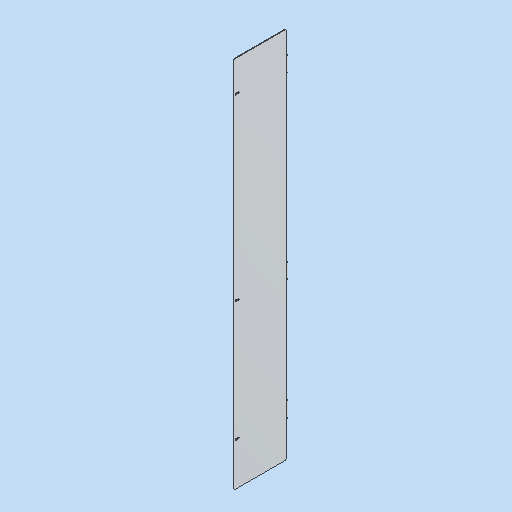
# Autodesk Inventor part: MM0948AN180_G01_108
Saved by Autodesk Inventor 2023.3 (Build 273359000, 359)
## iProperties
Created: 2023-08-14
Part Number: MM0948AN180_G01_108
Material: 3.3535 AlMg3 - AW 5754 (Blech)
Description: =<RBPARTNOTITLE2>
Document SubType Name: Sheet Metal
Designer: RIC7AN
Mass: 965.696 g
Surface Area: 3636.47 cm^2
Volume: 357.798 cm^3
Density: 2.699 g/cm^3
Flat Pattern Width: 19.1095 cm
Flat Pattern Length: 111.3 cm
Flat Pattern Area: 2126.88 cm^2
Sheet Metal Rule: Standard_mm
Sheet Metal Width: 191,095 mm
Sheet Metal Length: 1113,000 mm
Sheet Metal Area: 212688,390 mm^2
Appearance: Aluminium AnP
RBPARTMADEOF: 2 x 191,095 x 1113 (FM)
RBDRAWINGMISSINGSPEC: --
AnP_Kategorie: 1
RBPARTNOTITLE2: Anfertigungsteil
RBSURFACE: --
RBPARTNOTITLE1: manufactured part
RBSURFACE2: eloxiert E6/EV1 aluminiumfarbig
AnP_Material: =<Material>
RBMATERIAL: =<Material>
RBMATNO: =<Part Number>
RBPARTNO: SIEHE MNR
MaxAbmaße: 2 x 191,095 x 1113 (FM)
Author: RIC7AN
Keywords: =<RBPARTMADEOF>
Comments: =<RBSURFACE2>
Revision Number: 01
Autodesk Inventor part; units mm, degrees
ref_plane "YZ Plane" through (0, 0, 0) normal (1, 0, 0) x (0, 1, 0)
ref_plane "XZ Plane" through (0, 0, 0) normal (0, 1, 0) x (-1, 0, 0)
ref_plane "XY Plane" through (0, 0, 0) normal (0, 0, 1) x (1, 0, 0)
sketch "Skizze1" plane through (0, 0, 0) normal (0, 0, 1) x (1, 0, 0)
  line L0 (-31, 0) -> (0, 0)
  line L1 (0, 0) -> (0, -164)
  dimension "d0" = 31
  dimension "d1" = 164
  measures "d0" distance of L0.start L0.end
  measures "d1" distance of L0.end L1.end
contour flange "Konturlasche1" sketch "Skizze1" thickness 2 bend radius 3 width 1113 along (0, 0, 1) mid plane no both sides no wall seen from (-15.5, 0, 0) lies toward (0, -1, 0) curves L0 L1
bend "Biegung1"
corner "Ecke1"
sketch "Skizze2" plane through (0, -164, 1113) normal (1, 0, 0) x (0, 0, -1)
  line L0 (1113, 164) -> (0, 164) projected
  line L1 (0, 164) -> (70, 164)
  line L2 (70, 164) -> (70, 157)
  line L3 (70, 157) -> (0, 157)
  line L4 (0, 157) -> (0, 164)
  line L5 (1113, 164) -> (649.5, 164)
  line L6 (649.5, 164) -> (649.5, 157)
  line L7 (649.5, 157) -> (1113, 157)
  line L8 (1113, 157) -> (1113, 164)
  line L9 (115, 164) -> (604.5, 164)
  line L10 (604.5, 164) -> (604.5, 157)
  line L11 (604.5, 157) -> (115, 157)
  line L12 (115, 157) -> (115, 164)
  line L13 (1008, 164) -> (963, 164)
  line L14 (963, 164) -> (963, 157)
  line L15 (963, 157) -> (1008, 157)
  line L16 (1008, 157) -> (1008, 164)
  line L17 (1113, 159) -> (1113, 0) projected
  point P0 (649.5, 164)
  dimension "d13" = 70
  dimension "d14" = 7
  dimension "d15" = 45
  dimension "d16" = 45
  dimension "d19" = 534.5
  dimension "d20" = 45
  dimension "d21" = 150
  constraints: 32 end point, 8 parallel, 4 horizontal, 4 perpendicular, 3 point on line, 2 collinear
  measures "d13" distance of L2.end L3.end
  measures "d14" distance between parallel lines of L0 L3
  measures "d15" distance between parallel lines of L12 L2
  measures "d16" distance between parallel lines of L6 L10
  measures "d19" distance between parallel lines of L10 L2
  measures "d20" distance between parallel lines of L16 L14
  measures "d21" distance between parallel lines of L17 L14
extrude "Extrusion1" cut sketch "Skizze2" against normal through all contours L8 L7 L16 L0 | L14 L7 L6 L0 | L10 L11 L12 L0 | L2 L3 L4 L0
sketch "Skizze3" plane through (-31, -2, 1043) normal (0, -1, 0) x (1, 0, 0)
  line L0 (8, -22.5) -> (16, -22.5) construction
  line L1 (8, -19.2) -> (16, -19.2)
  line L2 (16, -25.8) -> (8, -25.8)
  arc A0 (8, -19.2) -> (8, -25.8) centre (8, -22.5) ccw
  arc A1 (16, -25.8) -> (16, -19.2) centre (16, -22.5) ccw
  line L3 (0, -45) -> (0, 0) projected
  line L4 (26, 0) -> (0, 0) projected
  line L5 (8, -557) -> (16, -557) construction
  line L6 (8, -553.7) -> (16, -553.7)
  line L7 (16, -560.3) -> (8, -560.3)
  arc A2 (8, -553.7) -> (8, -560.3) centre (8, -557) ccw
  arc A3 (16, -560.3) -> (16, -553.7) centre (16, -557) ccw
  line L8 (8, -915.5) -> (16, -915.5) construction
  line L9 (8, -912.2) -> (16, -912.2)
  line L10 (16, -918.8) -> (8, -918.8)
  arc A4 (8, -912.2) -> (8, -918.8) centre (8, -915.5) ccw
  arc A5 (16, -918.8) -> (16, -912.2) centre (16, -915.5) ccw
  line L11 (26, -534.5) -> (0, -534.5) projected
  line L12 (26, -893) -> (0, -893) projected
  line L13 (29, -1043) -> (29, 70) projected
  point P0 (31, -1043)
  point P1 (12, -22.5)
  point P2 (12, -557)
  point P3 (12, -915.5)
  dimension "d22" = 8
  dimension "d23" = 6.6
  dimension "d25" = 22.5
  dimension "d28" = 8
  dimension "d29" = 6.6
  dimension "d30" = 8
  dimension "d31" = 6.6
  dimension "d32" = 22.5
  dimension "d33" = 22.5
  dimension "d34" = 17
  constraints: 24 end point, 12 point on circle, 12 tangent, 6 centre point, 3 horizontal, 3 midpoint, 3 parallel, 2 vertical alignment
  measures "d22" distance of L0.start L0.end
  measures "d23" distance between parallel lines of L2 L1
  measures "d25" distance between parallel lines of L4 L0
  measures "d28" distance of L5.start L5.end
  measures "d29" distance between parallel lines of L7 L6
  measures "d30" distance of L8.start L8.end
  measures "d31" distance between parallel lines of L10 L9
  measures "d32" distance between parallel lines of L5 L11
  measures "d33" distance between parallel lines of L8 L12
  measures "d34" distance from line of L13 point (12, -22.5)
extrude "Ausschneiden1" cut sketch "Skizze3" against normal blind 2
fillet "Eckenrundung1" radius 5 10 edges at (-31, -1, 105) (-31, -1, 150) (-31, -1, 463.5) (-31, -1, 508.5) (-31, -1, 998) (-31, -1, 1043) (-1, -7, 1113) (-1, -164, 1113) (-1, -164, 0) (-1, -7, 0)
sketch "Skizze4" plane through (-2, -7, 508.5) normal (-1, 0, 0) x (0, 0, 1)
  line L0 (512, -189.8) -> (512, 39.8) projected
  line L1 (-22.5, -189.8) -> (-22.5, 39.8) projected
  line L2 (-381, -189.8) -> (-381, 39.8) projected
  line L3 (-381, -143) -> (-381, -151) construction
  line L4 (-383.25, -143) -> (-383.25, -151)
  line L5 (-378.75, -151) -> (-378.75, -143)
  arc A0 (-378.75, -143) -> (-383.25, -143) centre (-381, -143) ccw
  arc A1 (-383.25, -151) -> (-378.75, -151) centre (-381, -151) ccw
  line L6 (-22.5, -143) -> (-22.5, -151) construction
  line L7 (-24.75, -143) -> (-24.75, -151)
  line L8 (-20.25, -151) -> (-20.25, -143)
  arc A2 (-20.25, -143) -> (-24.75, -143) centre (-22.5, -143) ccw
  arc A3 (-24.75, -151) -> (-20.25, -151) centre (-22.5, -151) ccw
  line L9 (512, -143) -> (512, -151) construction
  line L10 (509.75, -143) -> (509.75, -151)
  line L11 (514.25, -151) -> (514.25, -143)
  arc A4 (514.25, -143) -> (509.75, -143) centre (512, -143) ccw
  arc A5 (509.75, -151) -> (514.25, -151) centre (512, -151) ccw
  line L12 (529.5, 7) -> (494.5, 7) projected
  point P0 (-508.5, 7)
  point P1 (-381, -147)
  point P2 (-22.5, -147)
  point P3 (512, -147)
  dimension "d36" = 8
  dimension "d37" = 4.5
  dimension "d40" = 8
  dimension "d41" = 4.5
  dimension "d42" = 8
  dimension "d43" = 4.5
  dimension "d44" = 154
  constraints: 24 end point, 12 point on circle, 12 tangent, 6 centre point, 3 midpoint, 3 parallel, 3 point on line, 3 vertical, 2 horizontal alignment
  measures "d36" distance of L3.start L3.end
  measures "d37" distance between parallel lines of L4 L5
  measures "d40" distance of L6.start L6.end
  measures "d41" distance between parallel lines of L7 L8
  measures "d42" distance of L9.start L9.end
  measures "d43" distance between parallel lines of L10 L11
  measures "d44" distance from line of point (512, -147) L12
extrude "Ausschneiden2" cut sketch "Skizze4" against normal blind 2
equation "\"d26\" = Stärke"
equation "\"d36\" = d42"
equation "\"d37\" = d43"
equation "\"d40\" = d42"
equation "\"d41\" = d43"
equation "\"d45\" = Stärke"
equation "\"d2\" = Stärke"
equation "\"d3\" = BreiteBiegungsfreistellung"
equation "\"d4\" = TiefeBiegungsfreistellung"
equation "\"d5\" = MinimalRest"
equation "\"d6\" = Übergangsradius"
equation "\"d8\" = Biegeradius"
equation "\"d10\" = GrößeEckenfreistellung"
equation "\"d11\" = Abstandsgröße"
equation "\"d12\" = JacobiRadiusGröße"
equation "\"Biegeradius\" = 1.5 * Stärke"
equation "\"BreiteBiegungsfreistellung\" = Stärke"
equation "\"TiefeBiegungsfreistellung\" = 0.5 * Stärke"
equation "\"GrößeEckenfreistellung\" = 4 * Stärke"
equation "\"MinimalRest\" = 2 * Stärke"
equation "\"Übergangsradius\" = Biegeradius"
equation "\"JacobiRadiusGröße\" = Biegeradius"
equation "\"Abstandsgröße\" = Stärke"
equation "\"Stärke\" = 2"
